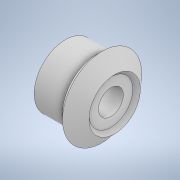
# Autodesk Inventor part: 24T
Saved by Autodesk Inventor 2021 (Build 250183000, 183)
## iProperties
Created: 2026-03-24
Part Number: 24T
Material: Genérico
Document SubType Name: Modeling
Designer: thepr
Density: 1 g/cm^3
Appearance: Valor por defecto
Author: thepr
Autodesk Inventor part; units mm, degrees
ref_plane "YZ Plane" through (0, 0, 0) normal (1, 0, 0) x (0, 1, 0)
ref_plane "XZ Plane" through (0, 0, 0) normal (0, 1, 0) x (-1, 0, 0)
ref_plane "XY Plane" through (0, 0, 0) normal (0, 0, 1) x (1, 0, 0)
sketch "Boceto1" plane through (0, 0, 0) normal (0, 0, 1) x (1, 0, 0)
  line L0 (-1.58, 0) -> (9.48, 0) construction
  line L1 (0, 2) -> (0, 5)
  line L2 (0, 5) -> (5, 5)
  line L3 (5, 5) -> (5, 5.445)
  line L4 (5, 5.445) -> (5.9, 6.355)
  line L5 (5.9, 6.355) -> (7.9, 4.1189)
  line L6 (7.3, 2) -> (0, 2)
  line L7 (7.9, 4.1189) -> (7.3, 3.505)
  line L8 (7.3, 3.505) -> (7.3, 2)
  line L9 (0, -1.271) -> (0, 7.626) projected
  point P0 (0, 0)
  point P1 (0, 3.5)
  dimension "d0" = 4
  dimension "d1" = 10
  dimension "d2" = 10.89
  dimension "d3" = 12.71
  dimension "d4" = 2.9
  dimension "d5" = 3
  dimension "d6" = 2
  dimension "d7" = 7.01
  dimension "d8" = 7.9
  dimension "d9" = 8.2379
  dimension "d10" = 0.6
  constraints: 16 end point, 4 perpendicular, 1 collinear, 1 midpoint, 1 point on line, 1 vertical
  measures "d0" diameter of L6 L0
  measures "d1" diameter of L2 L0
  measures "d2" diameter of L3.end L0
  measures "d3" diameter of L4.end L0
  measures "d4" horizontal distance of L5.end L3.end
  measures "d5" distance of L4.end L5.end
  measures "d6" horizontal distance of L5.end L4.end
  measures "d7" diameter of L7.end L0
  measures "d8" distance from line of L5.end L1
  measures "d9" diameter of L5.end L0
  measures "d10" horizontal distance of L5.end L7.end
revolve "Revolución1" add sketch "Boceto1" angle 360 about axis through (-10, 0, 0) along (1, 0, 0)
sketch "Boceto2" plane through (0, 0, 0) normal (0, 0, 1) x (1, 0, 0)
  circle A0 centre (2.5, 0) radius 1.5
  line L0 (0, -5) -> (0, 5) projected
  line L1 (-1.58, 0) -> (9.48, 0) projected
  point P0 (0, 0)
  dimension "d12" = 2.5
  dimension "d13" = 3
  constraints: 1 centre point, 1 point on line
  measures "d12" distance from line of L0 A0.centre
  measures "d13" diameter of A0
extrude "Extrusión1" cut sketch "Boceto2" against normal blind 10
